Autodesk Fusion 360 part; units mm, degrees
(part 4 of 8)
sketch "SW4 upper stop 1 profile" plane through (0, -1.6638, 19.017) normal (0, -0.087156, 0.996195) x (1, 0, 0)
  line L0 (12.0897, 53.4995) -> (13.0897, 53.4995)
  line L1 (13.0897, 53.4995) -> (13.0897, 58.2995)
  line L2 (13.0897, 58.2995) -> (12.0897, 58.2995)
  line L3 (12.0897, 58.2995) -> (12.0897, 53.4995)
  dimension "d2300" = 12.0897
  dimension "d2301" = 53.4995
  dimension "d2302" = 1
  dimension "d2303" = 4.8
  constraint horizontal L0
  constraint vertical L1
  constraint horizontal L2
  constraint vertical L3
  measures "d2300" horizontal distance of origin L0.start
  measures "d2301" vertical distance of origin L0.start
  measures "d2302" distance of L0.start L0.end
  measures "d2303" distance of L0.end L1.end
extrude "SW4 upper stop 1" add sketch "SW4 upper stop 1 profile" along normal blind 0.8 bodies 2
sketch "SW4 upper stop 2 profile" plane through (0, -1.6638, 19.017) normal (0, -0.087156, 0.996195) x (1, 0, 0)
  line L0 (18.0897, 53.4995) -> (19.0897, 53.4995)
  line L1 (19.0897, 53.4995) -> (19.0897, 58.2995)
  line L2 (19.0897, 58.2995) -> (18.0897, 58.2995)
  line L3 (18.0897, 58.2995) -> (18.0897, 53.4995)
  dimension "d2306" = 18.0897
  dimension "d2307" = 53.4995
  dimension "d2308" = 1
  dimension "d2309" = 4.8
  constraint horizontal L0
  constraint vertical L1
  constraint horizontal L2
  constraint vertical L3
  measures "d2306" horizontal distance of origin L0.start
  measures "d2307" vertical distance of origin L0.start
  measures "d2308" distance of L0.start L0.end
  measures "d2309" distance of L0.end L1.end
extrude "SW4 upper stop 2" add sketch "SW4 upper stop 2 profile" along normal blind 0.8 bodies 2
sketch "SW4 wire exit 1 profile" plane through (0, -1.5592, 17.8216) normal (0, -0.087156, 0.996195) x (1, 0, 0)
  line L0 (6.2897, 44.3995) -> (10.074, 44.3995)
  line L1 (10.074, 44.3995) -> (10.074, 52.1995)
  line L2 (10.074, 52.1995) -> (6.2897, 52.1995)
  line L3 (6.2897, 52.1995) -> (6.2897, 44.3995)
  dimension "d2312" = 6.2897
  dimension "d2313" = 44.3995
  dimension "d2314" = 3.7843
  dimension "d2315" = 7.8
  constraint horizontal L0
  constraint vertical L1
  constraint horizontal L2
  constraint vertical L3
  measures "d2312" horizontal distance of origin L0.start
  measures "d2313" vertical distance of origin L0.start
  measures "d2314" distance of L0.start L0.end
  measures "d2315" distance of L0.end L1.end
extrude "SW4 wire exit 1" cut sketch "SW4 wire exit 1 profile" against normal blind 5 bodies 2
sketch "SW4 wire exit 2 profile" plane through (0, -1.5592, 17.8216) normal (0, -0.087156, 0.996195) x (1, 0, 0)
  line L0 (21.1055, 44.3995) -> (24.8897, 44.3995)
  line L1 (24.8897, 44.3995) -> (24.8897, 52.1995)
  line L2 (24.8897, 52.1995) -> (21.1055, 52.1995)
  line L3 (21.1055, 52.1995) -> (21.1055, 44.3995)
  dimension "d2318" = 21.1055
  dimension "d2319" = 44.3995
  dimension "d2320" = 3.7843
  dimension "d2321" = 7.8
  constraint horizontal L0
  constraint vertical L1
  constraint horizontal L2
  constraint vertical L3
  measures "d2318" horizontal distance of origin L0.start
  measures "d2319" vertical distance of origin L0.start
  measures "d2320" distance of L0.start L0.end
  measures "d2321" distance of L0.end L1.end
extrude "SW4 wire exit 2" cut sketch "SW4 wire exit 2 profile" against normal blind 5 bodies 2
sketch "SW4 support 1 reinforced stem profile" plane through (0, 0, 2) normal (0, 0, 1) x (1, 0, 0)
  line L0 (11.8897, 44.4226) -> (14.2897, 44.4226)
  line L1 (14.2897, 44.4226) -> (14.2897, 49.4226)
  line L2 (14.2897, 49.4226) -> (11.8897, 49.4226)
  line L3 (11.8897, 49.4226) -> (11.8897, 44.4226)
  dimension "d2324" = 11.8897
  dimension "d2325" = 44.4226
  dimension "d2326" = 2.4
  dimension "d2327" = 5
  constraint horizontal L0
  constraint vertical L1
  constraint horizontal L2
  constraint vertical L3
  measures "d2324" horizontal distance of origin L0.start
  measures "d2325" vertical distance of origin L0.start
  measures "d2326" distance of L0.start L0.end
  measures "d2327" distance of L0.end L1.end
extrude "SW4 support 1 reinforced stem" add sketch "SW4 support 1 reinforced stem profile" along normal blind 13.8471 bodies 3
sketch "SW4 support 1 profile" plane through (0, 0, 2) normal (0, 0, 1) x (1, 0, 0)
  line L0 (12.5897, 45.4226) -> (13.5897, 45.4226)
  line L1 (13.5897, 45.4226) -> (13.5897, 48.4226)
  line L2 (13.5897, 48.4226) -> (12.5897, 48.4226)
  line L3 (12.5897, 48.4226) -> (12.5897, 45.4226)
  dimension "d2330" = 12.5897
  dimension "d2331" = 45.4226
  dimension "d2332" = 1
  dimension "d2333" = 3
  constraint horizontal L0
  constraint vertical L1
  constraint horizontal L2
  constraint vertical L3
  measures "d2330" horizontal distance of origin L0.start
  measures "d2331" vertical distance of origin L0.start
  measures "d2332" distance of L0.start L0.end
  measures "d2333" distance of L0.end L1.end
extrude "SW4 support 1" add sketch "SW4 support 1 profile" along normal blind 16.3471 bodies 3
sketch "SW4 support 1 cap profile" plane through (0, -1.1931, 13.6376) normal (0, -0.087156, 0.996195) x (1, 0, 0)
  line L0 (12.4897, 46.2995) -> (13.6897, 46.2995)
  line L1 (13.6897, 46.2995) -> (13.6897, 50.2995)
  line L2 (13.6897, 50.2995) -> (12.4897, 50.2995)
  line L3 (12.4897, 50.2995) -> (12.4897, 46.2995)
  dimension "d2336" = 12.4897
  dimension "d2337" = 46.2995
  dimension "d2338" = 1.2
  dimension "d2339" = 4
  constraint horizontal L0
  constraint vertical L1
  constraint horizontal L2
  constraint vertical L3
  measures "d2336" horizontal distance of origin L0.start
  measures "d2337" vertical distance of origin L0.start
  measures "d2338" distance of L0.start L0.end
  measures "d2339" distance of L0.end L1.end
extrude "SW4 support 1 inclined cap" cut sketch "SW4 support 1 cap profile" along normal blind 39.0612 bodies 3
sketch "SW4 support 2 reinforced stem profile" plane through (0, 0, 2) normal (0, 0, 1) x (1, 0, 0)
  line L0 (16.8897, 44.4226) -> (19.2897, 44.4226)
  line L1 (19.2897, 44.4226) -> (19.2897, 49.4226)
  line L2 (19.2897, 49.4226) -> (16.8897, 49.4226)
  line L3 (16.8897, 49.4226) -> (16.8897, 44.4226)
  dimension "d2342" = 16.8897
  dimension "d2343" = 44.4226
  dimension "d2344" = 2.4
  dimension "d2345" = 5
  constraint horizontal L0
  constraint vertical L1
  constraint horizontal L2
  constraint vertical L3
  measures "d2342" horizontal distance of origin L0.start
  measures "d2343" vertical distance of origin L0.start
  measures "d2344" distance of L0.start L0.end
  measures "d2345" distance of L0.end L1.end
extrude "SW4 support 2 reinforced stem" add sketch "SW4 support 2 reinforced stem profile" along normal blind 13.8471 bodies 3
sketch "SW4 support 2 profile" plane through (0, 0, 2) normal (0, 0, 1) x (1, 0, 0)
  line L0 (17.5897, 45.4226) -> (18.5897, 45.4226)
  line L1 (18.5897, 45.4226) -> (18.5897, 48.4226)
  line L2 (18.5897, 48.4226) -> (17.5897, 48.4226)
  line L3 (17.5897, 48.4226) -> (17.5897, 45.4226)
  dimension "d2348" = 17.5897
  dimension "d2349" = 45.4226
  dimension "d2350" = 1
  dimension "d2351" = 3
  constraint horizontal L0
  constraint vertical L1
  constraint horizontal L2
  constraint vertical L3
  measures "d2348" horizontal distance of origin L0.start
  measures "d2349" vertical distance of origin L0.start
  measures "d2350" distance of L0.start L0.end
  measures "d2351" distance of L0.end L1.end
extrude "SW4 support 2" add sketch "SW4 support 2 profile" along normal blind 16.3471 bodies 3
sketch "SW4 support 2 cap profile" plane through (0, -1.1931, 13.6376) normal (0, -0.087156, 0.996195) x (1, 0, 0)
  line L0 (17.4897, 46.2995) -> (18.6897, 46.2995)
  line L1 (18.6897, 46.2995) -> (18.6897, 50.2995)
  line L2 (18.6897, 50.2995) -> (17.4897, 50.2995)
  line L3 (17.4897, 50.2995) -> (17.4897, 46.2995)
  dimension "d2354" = 17.4897
  dimension "d2355" = 46.2995
  dimension "d2356" = 1.2
  dimension "d2357" = 4
  constraint horizontal L0
  constraint vertical L1
  constraint horizontal L2
  constraint vertical L3
  measures "d2354" horizontal distance of origin L0.start
  measures "d2355" vertical distance of origin L0.start
  measures "d2356" distance of L0.start L0.end
  measures "d2357" distance of L0.end L1.end
extrude "SW4 support 2 inclined cap" cut sketch "SW4 support 2 cap profile" along normal blind 39.0612 bodies 3
sketch "SW5 receiver profile" plane through (0, -2.1431, 24.4961) normal (0, -0.087156, 0.996195) x (1, 0, 0)
  line L0 (30.8, 42.1972) -> (49.2, 42.1972)
  line L1 (49.2, 42.1972) -> (49.2, 59.7972)
  line L2 (49.2, 59.7972) -> (30.8, 59.7972)
  line L3 (30.8, 59.7972) -> (30.8, 42.1972)
  dimension "d2360" = 30.8
  dimension "d2361" = 42.1972
  dimension "d2362" = 18.4
  dimension "d2363" = 17.6
  constraint horizontal L0
  constraint vertical L1
  constraint horizontal L2
  constraint vertical L3
  measures "d2360" horizontal distance of origin L0.start
  measures "d2361" vertical distance of origin L0.start
  measures "d2362" distance of L0.start L0.end
  measures "d2363" distance of L0.end L1.end
extrude "SW5 integrated receiver" add sketch "SW5 receiver profile" against normal blind 11.5 bodies 2
sketch "SW5 switch lower clearance profile" plane through (0, -2.1431, 24.4961) normal (0, -0.087156, 0.996195) x (1, 0, 0)
  line L0 (32, 42.9972) -> (48, 42.9972)
  line L1 (48, 42.9972) -> (48, 58.9972)
  line L2 (48, 58.9972) -> (32, 58.9972)
  line L3 (32, 58.9972) -> (32, 42.9972)
  dimension "d2366" = 32
  dimension "d2367" = 42.9972
  dimension "d2368" = 16
  dimension "d2369" = 16
  constraint horizontal L0
  constraint vertical L1
  constraint horizontal L2
  constraint vertical L3
  measures "d2366" horizontal distance of origin L0.start
  measures "d2367" vertical distance of origin L0.start
  measures "d2368" distance of L0.start L0.end
  measures "d2369" distance of L0.end L1.end
extrude "SW5 switch lower clearance" cut sketch "SW5 switch lower clearance profile" against normal blind 5.5 bodies 2
sketch "SW5 holder pocket profile" plane through (0, -1.6638, 19.017) normal (0, -0.087156, 0.996195) x (1, 0, 0)
  line L0 (34.374, 44.425) -> (45.8055, 44.425)
  line L1 (45.8055, 44.425) -> (45.8055, 54.5741)
  line L2 (45.8055, 54.5741) -> (34.374, 54.5741)
  line L3 (34.374, 54.5741) -> (34.374, 44.425)
  dimension "d2372" = 34.374
  dimension "d2373" = 44.425
  dimension "d2374" = 11.4315
  dimension "d2375" = 10.1491
  constraint horizontal L0
  constraint vertical L1
  constraint horizontal L2
  constraint vertical L3
  measures "d2372" horizontal distance of origin L0.start
  measures "d2373" vertical distance of origin L0.start
  measures "d2374" distance of L0.start L0.end
  measures "d2375" distance of L0.end L1.end
extrude "SW5 open-bottom holder pocket" cut sketch "SW5 holder pocket profile" against normal blind 6.2 bodies 2
sketch "SW5 spring 1 release 1 profile" plane through (0, -2.056, 23.4999) normal (0, -0.087156, 0.996195) x (1, 0, 0)
  line L0 (30.7897, 51.5995) -> (34.374, 51.5995)
  line L1 (34.374, 51.5995) -> (34.374, 52.1995)
  line L2 (34.374, 52.1995) -> (30.7897, 52.1995)
  line L3 (30.7897, 52.1995) -> (30.7897, 51.5995)
  dimension "d2378" = 30.7897
  dimension "d2379" = 51.5995
  dimension "d2380" = 3.5843
  dimension "d2381" = 0.6
  constraint horizontal L0
  constraint vertical L1
  constraint horizontal L2
  constraint vertical L3
  measures "d2378" horizontal distance of origin L0.start
  measures "d2379" vertical distance of origin L0.start
  measures "d2380" distance of L0.start L0.end
  measures "d2381" distance of L0.end L1.end
extrude "SW5 spring 1 release 1" cut sketch "SW5 spring 1 release 1 profile" against normal blind 10.7 bodies 2
sketch "SW5 spring 1 release 2 profile" plane through (0, -2.056, 23.4999) normal (0, -0.087156, 0.996195) x (1, 0, 0)
  line L0 (30.7897, 54.1995) -> (34.374, 54.1995)
  line L1 (34.374, 54.1995) -> (34.374, 54.7995)
  line L2 (34.374, 54.7995) -> (30.7897, 54.7995)
  line L3 (30.7897, 54.7995) -> (30.7897, 54.1995)
  dimension "d2384" = 30.7897
  dimension "d2385" = 54.1995
  dimension "d2386" = 3.5843
  dimension "d2387" = 0.6
  constraint horizontal L0
  constraint vertical L1
  constraint horizontal L2
  constraint vertical L3
  measures "d2384" horizontal distance of origin L0.start
  measures "d2385" vertical distance of origin L0.start
  measures "d2386" distance of L0.start L0.end
  measures "d2387" distance of L0.end L1.end
extrude "SW5 spring 1 release 2" cut sketch "SW5 spring 1 release 2 profile" against normal blind 10.7 bodies 2
sketch "SW5 spring 1 inner clearance profile" plane through (0, -1.6638, 19.017) normal (0, -0.087156, 0.996195) x (1, 0, 0)
  line L0 (31.6897, 52.1995) -> (34.374, 52.1995)
  line L1 (34.374, 52.1995) -> (34.374, 54.1995)
  line L2 (34.374, 54.1995) -> (31.6897, 54.1995)
  line L3 (31.6897, 54.1995) -> (31.6897, 52.1995)
  dimension "d2390" = 31.6897
  dimension "d2391" = 52.1995
  dimension "d2392" = 2.6843
  dimension "d2393" = 2
  constraint horizontal L0
  constraint vertical L1
  constraint horizontal L2
  constraint vertical L3
  measures "d2390" horizontal distance of origin L0.start
  measures "d2391" vertical distance of origin L0.start
  measures "d2392" distance of L0.start L0.end
  measures "d2393" distance of L0.end L1.end
extrude "SW5 spring 1 inner clearance" cut sketch "SW5 spring 1 inner clearance profile" against normal blind 6.2 bodies 2
sketch "SW5 spring 1 hook profile" plane through (0, -1.2106, 13.8368) normal (0, -0.087156, 0.996195) x (1, 0, 0)
  line L0 (30.8897, 52.1995) -> (34.874, 52.1995)
  line L1 (34.874, 52.1995) -> (34.874, 54.1995)
  line L2 (34.874, 54.1995) -> (30.8897, 54.1995)
  line L3 (30.8897, 54.1995) -> (30.8897, 52.1995)
  dimension "d2396" = 30.8897
  dimension "d2397" = 52.1995
  dimension "d2398" = 3.9843
  dimension "d2399" = 2
  constraint horizontal L0
  constraint vertical L1
  constraint horizontal L2
  constraint vertical L3
  measures "d2396" horizontal distance of origin L0.start
  measures "d2397" vertical distance of origin L0.start
  measures "d2398" distance of L0.start L0.end
  measures "d2399" distance of L0.end L1.end
extrude "SW5 spring 1 retaining hook" add sketch "SW5 spring 1 hook profile" against normal blind 0.8 bodies 2
chamfer "SW5 spring 1 45 degree lead-in" distance 0.35 angle 45 1 edges at (34.874, 51.8562, 17.6765) tangent chain off on bodies 2
sketch "SW5 spring 2 release 1 profile" plane through (0, -2.056, 23.4999) normal (0, -0.087156, 0.996195) x (1, 0, 0)
  line L0 (45.8055, 51.5995) -> (49.3897, 51.5995)
  line L1 (49.3897, 51.5995) -> (49.3897, 52.1995)
  line L2 (49.3897, 52.1995) -> (45.8055, 52.1995)
  line L3 (45.8055, 52.1995) -> (45.8055, 51.5995)
  dimension "d2403" = 45.8055
  dimension "d2404" = 51.5995
  dimension "d2405" = 3.5843
  dimension "d2406" = 0.6
  constraint horizontal L0
  constraint vertical L1
  constraint horizontal L2
  constraint vertical L3
  measures "d2403" horizontal distance of origin L0.start
  measures "d2404" vertical distance of origin L0.start
  measures "d2405" distance of L0.start L0.end
  measures "d2406" distance of L0.end L1.end
extrude "SW5 spring 2 release 1" cut sketch "SW5 spring 2 release 1 profile" against normal blind 10.7 bodies 2
sketch "SW5 spring 2 release 2 profile" plane through (0, -2.056, 23.4999) normal (0, -0.087156, 0.996195) x (1, 0, 0)
  line L0 (45.8055, 54.1995) -> (49.3897, 54.1995)
  line L1 (49.3897, 54.1995) -> (49.3897, 54.7995)
  line L2 (49.3897, 54.7995) -> (45.8055, 54.7995)
  line L3 (45.8055, 54.7995) -> (45.8055, 54.1995)
  dimension "d2409" = 45.8055
  dimension "d2410" = 54.1995
  dimension "d2411" = 3.5843
  dimension "d2412" = 0.6
  constraint horizontal L0
  constraint vertical L1
  constraint horizontal L2
  constraint vertical L3
  measures "d2409" horizontal distance of origin L0.start
  measures "d2410" vertical distance of origin L0.start
  measures "d2411" distance of L0.start L0.end
  measures "d2412" distance of L0.end L1.end
extrude "SW5 spring 2 release 2" cut sketch "SW5 spring 2 release 2 profile" against normal blind 10.7 bodies 2
sketch "SW5 spring 2 inner clearance profile" plane through (0, -1.6638, 19.017) normal (0, -0.087156, 0.996195) x (1, 0, 0)
  line L0 (45.8055, 52.1995) -> (48.4897, 52.1995)
  line L1 (48.4897, 52.1995) -> (48.4897, 54.1995)
  line L2 (48.4897, 54.1995) -> (45.8055, 54.1995)
  line L3 (45.8055, 54.1995) -> (45.8055, 52.1995)
  dimension "d2415" = 45.8055
  dimension "d2416" = 52.1995
  dimension "d2417" = 2.6843
  dimension "d2418" = 2
  constraint horizontal L0
  constraint vertical L1
  constraint horizontal L2
  constraint vertical L3
  measures "d2415" horizontal distance of origin L0.start
  measures "d2416" vertical distance of origin L0.start
  measures "d2417" distance of L0.start L0.end
  measures "d2418" distance of L0.end L1.end
extrude "SW5 spring 2 inner clearance" cut sketch "SW5 spring 2 inner clearance profile" against normal blind 6.2 bodies 2
sketch "SW5 spring 2 hook profile" plane through (0, -1.2106, 13.8368) normal (0, -0.087156, 0.996195) x (1, 0, 0)
  line L0 (45.3055, 52.1995) -> (49.2897, 52.1995)
  line L1 (49.2897, 52.1995) -> (49.2897, 54.1995)
  line L2 (49.2897, 54.1995) -> (45.3055, 54.1995)
  line L3 (45.3055, 54.1995) -> (45.3055, 52.1995)
  dimension "d2421" = 45.3055
  dimension "d2422" = 52.1995
  dimension "d2423" = 3.9843
  dimension "d2424" = 2
  constraint horizontal L0
  constraint vertical L1
  constraint horizontal L2
  constraint vertical L3
  measures "d2421" horizontal distance of origin L0.start
  measures "d2422" vertical distance of origin L0.start
  measures "d2423" distance of L0.start L0.end
  measures "d2424" distance of L0.end L1.end
extrude "SW5 spring 2 retaining hook" add sketch "SW5 spring 2 hook profile" against normal blind 0.8 bodies 2
chamfer "SW5 spring 2 45 degree lead-in" distance 0.35 angle 45 1 edges at (45.3055, 51.8562, 17.6765) tangent chain off on bodies 2
sketch "SW5 upper stop 1 profile" plane through (0, -1.6638, 19.017) normal (0, -0.087156, 0.996195) x (1, 0, 0)
  line L0 (36.5897, 53.4995) -> (37.5897, 53.4995)
  line L1 (37.5897, 53.4995) -> (37.5897, 58.2995)
  line L2 (37.5897, 58.2995) -> (36.5897, 58.2995)
  line L3 (36.5897, 58.2995) -> (36.5897, 53.4995)
  dimension "d2428" = 36.5897
  dimension "d2429" = 53.4995
  dimension "d2430" = 1
  dimension "d2431" = 4.8
  constraint horizontal L0
  constraint vertical L1
  constraint horizontal L2
  constraint vertical L3
  measures "d2428" horizontal distance of origin L0.start
  measures "d2429" vertical distance of origin L0.start
  measures "d2430" distance of L0.start L0.end
  measures "d2431" distance of L0.end L1.end
extrude "SW5 upper stop 1" add sketch "SW5 upper stop 1 profile" along normal blind 0.8 bodies 2
sketch "SW5 upper stop 2 profile" plane through (0, -1.6638, 19.017) normal (0, -0.087156, 0.996195) x (1, 0, 0)
  line L0 (42.5897, 53.4995) -> (43.5897, 53.4995)
  line L1 (43.5897, 53.4995) -> (43.5897, 58.2995)
  line L2 (43.5897, 58.2995) -> (42.5897, 58.2995)
  line L3 (42.5897, 58.2995) -> (42.5897, 53.4995)
  dimension "d2434" = 42.5897
  dimension "d2435" = 53.4995
  dimension "d2436" = 1
  dimension "d2437" = 4.8
  constraint horizontal L0
  constraint vertical L1
  constraint horizontal L2
  constraint vertical L3
  measures "d2434" horizontal distance of origin L0.start
  measures "d2435" vertical distance of origin L0.start
  measures "d2436" distance of L0.start L0.end
  measures "d2437" distance of L0.end L1.end
extrude "SW5 upper stop 2" add sketch "SW5 upper stop 2 profile" along normal blind 0.8 bodies 2
sketch "SW5 wire exit 1 profile" plane through (0, -1.5592, 17.8216) normal (0, -0.087156, 0.996195) x (1, 0, 0)
  line L0 (30.7897, 44.3995) -> (34.574, 44.3995)
  line L1 (34.574, 44.3995) -> (34.574, 52.1995)
  line L2 (34.574, 52.1995) -> (30.7897, 52.1995)
  line L3 (30.7897, 52.1995) -> (30.7897, 44.3995)
  dimension "d2440" = 30.7897
  dimension "d2441" = 44.3995
  dimension "d2442" = 3.7843
  dimension "d2443" = 7.8
  constraint horizontal L0
  constraint vertical L1
  constraint horizontal L2
  constraint vertical L3
  measures "d2440" horizontal distance of origin L0.start
  measures "d2441" vertical distance of origin L0.start
  measures "d2442" distance of L0.start L0.end
  measures "d2443" distance of L0.end L1.end
extrude "SW5 wire exit 1" cut sketch "SW5 wire exit 1 profile" against normal blind 5 bodies 2
sketch "SW5 wire exit 2 profile" plane through (0, -1.5592, 17.8216) normal (0, -0.087156, 0.996195) x (1, 0, 0)
  line L0 (45.6055, 44.3995) -> (49.3897, 44.3995)
  line L1 (49.3897, 44.3995) -> (49.3897, 52.1995)
  line L2 (49.3897, 52.1995) -> (45.6055, 52.1995)
  line L3 (45.6055, 52.1995) -> (45.6055, 44.3995)
  dimension "d2446" = 45.6055
  dimension "d2447" = 44.3995
  dimension "d2448" = 3.7843
  dimension "d2449" = 7.8
  constraint horizontal L0
  constraint vertical L1
  constraint horizontal L2
  constraint vertical L3
  measures "d2446" horizontal distance of origin L0.start
  measures "d2447" vertical distance of origin L0.start
  measures "d2448" distance of L0.start L0.end
  measures "d2449" distance of L0.end L1.end
extrude "SW5 wire exit 2" cut sketch "SW5 wire exit 2 profile" against normal blind 5 bodies 2
sketch "SW5 support 1 reinforced stem profile" plane through (0, 0, 2) normal (0, 0, 1) x (1, 0, 0)
  line L0 (36.3897, 44.4226) -> (38.7897, 44.4226)
  line L1 (38.7897, 44.4226) -> (38.7897, 49.4226)
  line L2 (38.7897, 49.4226) -> (36.3897, 49.4226)
  line L3 (36.3897, 49.4226) -> (36.3897, 44.4226)
  dimension "d2452" = 36.3897
  dimension "d2453" = 44.4226
  dimension "d2454" = 2.4
  dimension "d2455" = 5
  constraint horizontal L0
  constraint vertical L1
  constraint horizontal L2
  constraint vertical L3
  measures "d2452" horizontal distance of origin L0.start
  measures "d2453" vertical distance of origin L0.start
  measures "d2454" distance of L0.start L0.end
  measures "d2455" distance of L0.end L1.end
extrude "SW5 support 1 reinforced stem" add sketch "SW5 support 1 reinforced stem profile" along normal blind 13.8471 bodies 3
sketch "SW5 support 1 profile" plane through (0, 0, 2) normal (0, 0, 1) x (1, 0, 0)
  line L0 (37.0897, 45.4226) -> (38.0897, 45.4226)
  line L1 (38.0897, 45.4226) -> (38.0897, 48.4226)
  line L2 (38.0897, 48.4226) -> (37.0897, 48.4226)
  line L3 (37.0897, 48.4226) -> (37.0897, 45.4226)
  dimension "d2458" = 37.0897
  dimension "d2459" = 45.4226
  dimension "d2460" = 1
  dimension "d2461" = 3
  constraint horizontal L0
  constraint vertical L1
  constraint horizontal L2
  constraint vertical L3
  measures "d2458" horizontal distance of origin L0.start
  measures "d2459" vertical distance of origin L0.start
  measures "d2460" distance of L0.start L0.end
  measures "d2461" distance of L0.end L1.end
extrude "SW5 support 1" add sketch "SW5 support 1 profile" along normal blind 16.3471 bodies 3
sketch "SW5 support 1 cap profile" plane through (0, -1.1931, 13.6376) normal (0, -0.087156, 0.996195) x (1, 0, 0)
  line L0 (36.9897, 46.2995) -> (38.1897, 46.2995)
  line L1 (38.1897, 46.2995) -> (38.1897, 50.2995)
  line L2 (38.1897, 50.2995) -> (36.9897, 50.2995)
  line L3 (36.9897, 50.2995) -> (36.9897, 46.2995)
  dimension "d2464" = 36.9897
  dimension "d2465" = 46.2995
  dimension "d2466" = 1.2
  dimension "d2467" = 4
  constraint horizontal L0
  constraint vertical L1
  constraint horizontal L2
  constraint vertical L3
  measures "d2464" horizontal distance of origin L0.start
  measures "d2465" vertical distance of origin L0.start
  measures "d2466" distance of L0.start L0.end
  measures "d2467" distance of L0.end L1.end
extrude "SW5 support 1 inclined cap" cut sketch "SW5 support 1 cap profile" along normal blind 39.0612 bodies 3
sketch "SW5 support 2 reinforced stem profile" plane through (0, 0, 2) normal (0, 0, 1) x (1, 0, 0)
  line L0 (41.3897, 44.4226) -> (43.7897, 44.4226)
  line L1 (43.7897, 44.4226) -> (43.7897, 49.4226)
  line L2 (43.7897, 49.4226) -> (41.3897, 49.4226)
  line L3 (41.3897, 49.4226) -> (41.3897, 44.4226)
  dimension "d2470" = 41.3897
  dimension "d2471" = 44.4226
  dimension "d2472" = 2.4
  dimension "d2473" = 5
  constraint horizontal L0
  constraint vertical L1
  constraint horizontal L2
  constraint vertical L3
  measures "d2470" horizontal distance of origin L0.start
  measures "d2471" vertical distance of origin L0.start
  measures "d2472" distance of L0.start L0.end
  measures "d2473" distance of L0.end L1.end
extrude "SW5 support 2 reinforced stem" add sketch "SW5 support 2 reinforced stem profile" along normal blind 13.8471 bodies 3
sketch "SW5 support 2 profile" plane through (0, 0, 2) normal (0, 0, 1) x (1, 0, 0)
  line L0 (42.0897, 45.4226) -> (43.0897, 45.4226)
  line L1 (43.0897, 45.4226) -> (43.0897, 48.4226)
  line L2 (43.0897, 48.4226) -> (42.0897, 48.4226)
  line L3 (42.0897, 48.4226) -> (42.0897, 45.4226)
  dimension "d2476" = 42.0897
  dimension "d2477" = 45.4226
  dimension "d2478" = 1
  dimension "d2479" = 3
  constraint horizontal L0
  constraint vertical L1
  constraint horizontal L2
  constraint vertical L3
  measures "d2476" horizontal distance of origin L0.start
  measures "d2477" vertical distance of origin L0.start
  measures "d2478" distance of L0.start L0.end
  measures "d2479" distance of L0.end L1.end
extrude "SW5 support 2" add sketch "SW5 support 2 profile" along normal blind 16.3471 bodies 3
sketch "SW5 support 2 cap profile" plane through (0, -1.1931, 13.6376) normal (0, -0.087156, 0.996195) x (1, 0, 0)
  line L0 (41.9897, 46.2995) -> (43.1897, 46.2995)
  line L1 (43.1897, 46.2995) -> (43.1897, 50.2995)
  line L2 (43.1897, 50.2995) -> (41.9897, 50.2995)
  line L3 (41.9897, 50.2995) -> (41.9897, 46.2995)
  dimension "d2482" = 41.9897
  dimension "d2483" = 46.2995
  dimension "d2484" = 1.2
  dimension "d2485" = 4
  constraint horizontal L0
  constraint vertical L1
  constraint horizontal L2
  constraint vertical L3
  measures "d2482" horizontal distance of origin L0.start
  measures "d2483" vertical distance of origin L0.start
  measures "d2484" distance of L0.start L0.end
  measures "d2485" distance of L0.end L1.end
extrude "SW5 support 2 inclined cap" cut sketch "SW5 support 2 cap profile" along normal blind 39.0612 bodies 3
sketch "SW6 receiver profile" plane through (0, -2.1431, 24.4961) normal (0, -0.087156, 0.996195) x (1, 0, 0)
  line L0 (55.3, 42.1972) -> (73.7, 42.1972)
  line L1 (73.7, 42.1972) -> (73.7, 59.7972)
  line L2 (73.7, 59.7972) -> (55.3, 59.7972)
  line L3 (55.3, 59.7972) -> (55.3, 42.1972)
  dimension "d2488" = 55.3
  dimension "d2489" = 42.1972
  dimension "d2490" = 18.4
  dimension "d2491" = 17.6
  constraint horizontal L0
  constraint vertical L1
  constraint horizontal L2
  constraint vertical L3
  measures "d2488" horizontal distance of origin L0.start
  measures "d2489" vertical distance of origin L0.start
  measures "d2490" distance of L0.start L0.end
  measures "d2491" distance of L0.end L1.end
extrude "SW6 integrated receiver" add sketch "SW6 receiver profile" against normal blind 11.5 bodies 2
sketch "SW6 switch lower clearance profile" plane through (0, -2.1431, 24.4961) normal (0, -0.087156, 0.996195) x (1, 0, 0)
  line L0 (56.5, 42.9972) -> (72.5, 42.9972)
  line L1 (72.5, 42.9972) -> (72.5, 58.9972)
  line L2 (72.5, 58.9972) -> (56.5, 58.9972)
  line L3 (56.5, 58.9972) -> (56.5, 42.9972)
  dimension "d2494" = 56.5
  dimension "d2495" = 42.9972
  dimension "d2496" = 16
  dimension "d2497" = 16
  constraint horizontal L0
  constraint vertical L1
  constraint horizontal L2
  constraint vertical L3
  measures "d2494" horizontal distance of origin L0.start
  measures "d2495" vertical distance of origin L0.start
  measures "d2496" distance of L0.start L0.end
  measures "d2497" distance of L0.end L1.end
extrude "SW6 switch lower clearance" cut sketch "SW6 switch lower clearance profile" against normal blind 5.5 bodies 2
sketch "SW6 holder pocket profile" plane through (0, -1.6638, 19.017) normal (0, -0.087156, 0.996195) x (1, 0, 0)
  line L0 (58.874, 44.425) -> (70.3055, 44.425)
  line L1 (70.3055, 44.425) -> (70.3055, 54.5741)
  line L2 (70.3055, 54.5741) -> (58.874, 54.5741)
  line L3 (58.874, 54.5741) -> (58.874, 44.425)
  dimension "d2500" = 58.874
  dimension "d2501" = 44.425
  dimension "d2502" = 11.4315
  dimension "d2503" = 10.1491
  constraint horizontal L0
  constraint vertical L1
  constraint horizontal L2
  constraint vertical L3
  measures "d2500" horizontal distance of origin L0.start
  measures "d2501" vertical distance of origin L0.start
  measures "d2502" distance of L0.start L0.end
  measures "d2503" distance of L0.end L1.end
extrude "SW6 open-bottom holder pocket" cut sketch "SW6 holder pocket profile" against normal blind 6.2 bodies 2
sketch "SW6 spring 1 release 1 profile" plane through (0, -2.056, 23.4999) normal (0, -0.087156, 0.996195) x (1, 0, 0)
  line L0 (55.2897, 51.5995) -> (58.874, 51.5995)
  line L1 (58.874, 51.5995) -> (58.874, 52.1995)
  line L2 (58.874, 52.1995) -> (55.2897, 52.1995)
  line L3 (55.2897, 52.1995) -> (55.2897, 51.5995)
  dimension "d2506" = 55.2897
  dimension "d2507" = 51.5995
  dimension "d2508" = 3.5843
  dimension "d2509" = 0.6
  constraint horizontal L0
  constraint vertical L1
  constraint horizontal L2
  constraint vertical L3
  measures "d2506" horizontal distance of origin L0.start
  measures "d2507" vertical distance of origin L0.start
  measures "d2508" distance of L0.start L0.end
  measures "d2509" distance of L0.end L1.end
extrude "SW6 spring 1 release 1" cut sketch "SW6 spring 1 release 1 profile" against normal blind 10.7 bodies 2
sketch "SW6 spring 1 release 2 profile" plane through (0, -2.056, 23.4999) normal (0, -0.087156, 0.996195) x (1, 0, 0)
  line L0 (55.2897, 54.1995) -> (58.874, 54.1995)
  line L1 (58.874, 54.1995) -> (58.874, 54.7995)
  line L2 (58.874, 54.7995) -> (55.2897, 54.7995)
  line L3 (55.2897, 54.7995) -> (55.2897, 54.1995)
  dimension "d2512" = 55.2897
  dimension "d2513" = 54.1995
  dimension "d2514" = 3.5843
  dimension "d2515" = 0.6
  constraint horizontal L0
  constraint vertical L1
  constraint horizontal L2
  constraint vertical L3
  measures "d2512" horizontal distance of origin L0.start
  measures "d2513" vertical distance of origin L0.start
  measures "d2514" distance of L0.start L0.end
  measures "d2515" distance of L0.end L1.end
extrude "SW6 spring 1 release 2" cut sketch "SW6 spring 1 release 2 profile" against normal blind 10.7 bodies 2
sketch "SW6 spring 1 inner clearance profile" plane through (0, -1.6638, 19.017) normal (0, -0.087156, 0.996195) x (1, 0, 0)
  line L0 (56.1897, 52.1995) -> (58.874, 52.1995)
  line L1 (58.874, 52.1995) -> (58.874, 54.1995)
  line L2 (58.874, 54.1995) -> (56.1897, 54.1995)
  line L3 (56.1897, 54.1995) -> (56.1897, 52.1995)
  dimension "d2518" = 56.1897
  dimension "d2519" = 52.1995
  dimension "d2520" = 2.6843
  dimension "d2521" = 2
  constraint horizontal L0
  constraint vertical L1
  constraint horizontal L2
  constraint vertical L3
  measures "d2518" horizontal distance of origin L0.start
  measures "d2519" vertical distance of origin L0.start
  measures "d2520" distance of L0.start L0.end
  measures "d2521" distance of L0.end L1.end
extrude "SW6 spring 1 inner clearance" cut sketch "SW6 spring 1 inner clearance profile" against normal blind 6.2 bodies 2
sketch "SW6 spring 1 hook profile" plane through (0, -1.2106, 13.8368) normal (0, -0.087156, 0.996195) x (1, 0, 0)
  line L0 (55.3897, 52.1995) -> (59.374, 52.1995)
  line L1 (59.374, 52.1995) -> (59.374, 54.1995)
  line L2 (59.374, 54.1995) -> (55.3897, 54.1995)
  line L3 (55.3897, 54.1995) -> (55.3897, 52.1995)
  dimension "d2524" = 55.3897
  dimension "d2525" = 52.1995
  dimension "d2526" = 3.9843
  dimension "d2527" = 2
  constraint horizontal L0
  constraint vertical L1
  constraint horizontal L2
  constraint vertical L3
  measures "d2524" horizontal distance of origin L0.start
  measures "d2525" vertical distance of origin L0.start
  measures "d2526" distance of L0.start L0.end
  measures "d2527" distance of L0.end L1.end
extrude "SW6 spring 1 retaining hook" add sketch "SW6 spring 1 hook profile" against normal blind 0.8 bodies 2
chamfer "SW6 spring 1 45 degree lead-in" distance 0.35 angle 45 1 edges at (59.374, 51.8562, 17.6765) tangent chain off on bodies 2
sketch "SW6 spring 2 release 1 profile" plane through (0, -2.056, 23.4999) normal (0, -0.087156, 0.996195) x (1, 0, 0)
  line L0 (70.3055, 51.5995) -> (73.8897, 51.5995)
  line L1 (73.8897, 51.5995) -> (73.8897, 52.1995)
  line L2 (73.8897, 52.1995) -> (70.3055, 52.1995)
  line L3 (70.3055, 52.1995) -> (70.3055, 51.5995)
  dimension "d2531" = 70.3055
  dimension "d2532" = 51.5995
  dimension "d2533" = 3.5843
  dimension "d2534" = 0.6
  constraint horizontal L0
  constraint vertical L1
  constraint horizontal L2
  constraint vertical L3
  measures "d2531" horizontal distance of origin L0.start
  measures "d2532" vertical distance of origin L0.start
  measures "d2533" distance of L0.start L0.end
  measures "d2534" distance of L0.end L1.end
extrude "SW6 spring 2 release 1" cut sketch "SW6 spring 2 release 1 profile" against normal blind 10.7 bodies 2
sketch "SW6 spring 2 release 2 profile" plane through (0, -2.056, 23.4999) normal (0, -0.087156, 0.996195) x (1, 0, 0)
  line L0 (70.3055, 54.1995) -> (73.8897, 54.1995)
  line L1 (73.8897, 54.1995) -> (73.8897, 54.7995)
  line L2 (73.8897, 54.7995) -> (70.3055, 54.7995)
  line L3 (70.3055, 54.7995) -> (70.3055, 54.1995)
  dimension "d2537" = 70.3055
  dimension "d2538" = 54.1995
  dimension "d2539" = 3.5843
  dimension "d2540" = 0.6
  constraint horizontal L0
  constraint vertical L1
  constraint horizontal L2
  constraint vertical L3
  measures "d2537" horizontal distance of origin L0.start
  measures "d2538" vertical distance of origin L0.start
  measures "d2539" distance of L0.start L0.end
  measures "d2540" distance of L0.end L1.end
extrude "SW6 spring 2 release 2" cut sketch "SW6 spring 2 release 2 profile" against normal blind 10.7 bodies 2
sketch "SW6 spring 2 inner clearance profile" plane through (0, -1.6638, 19.017) normal (0, -0.087156, 0.996195) x (1, 0, 0)
  line L0 (70.3055, 52.1995) -> (72.9897, 52.1995)
  line L1 (72.9897, 52.1995) -> (72.9897, 54.1995)
  line L2 (72.9897, 54.1995) -> (70.3055, 54.1995)
  line L3 (70.3055, 54.1995) -> (70.3055, 52.1995)
  dimension "d2543" = 70.3055
  dimension "d2544" = 52.1995
  dimension "d2545" = 2.6843
  dimension "d2546" = 2
  constraint horizontal L0
  constraint vertical L1
  constraint horizontal L2
  constraint vertical L3
  measures "d2543" horizontal distance of origin L0.start
  measures "d2544" vertical distance of origin L0.start
  measures "d2545" distance of L0.start L0.end
  measures "d2546" distance of L0.end L1.end
extrude "SW6 spring 2 inner clearance" cut sketch "SW6 spring 2 inner clearance profile" against normal blind 6.2 bodies 2
sketch "SW6 spring 2 hook profile" plane through (0, -1.2106, 13.8368) normal (0, -0.087156, 0.996195) x (1, 0, 0)
  line L0 (69.8055, 52.1995) -> (73.7897, 52.1995)
  line L1 (73.7897, 52.1995) -> (73.7897, 54.1995)
  line L2 (73.7897, 54.1995) -> (69.8055, 54.1995)
  line L3 (69.8055, 54.1995) -> (69.8055, 52.1995)
  dimension "d2549" = 69.8055
  dimension "d2550" = 52.1995
  dimension "d2551" = 3.9843
  dimension "d2552" = 2
  constraint horizontal L0
  constraint vertical L1
  constraint horizontal L2
  constraint vertical L3
  measures "d2549" horizontal distance of origin L0.start
  measures "d2550" vertical distance of origin L0.start
  measures "d2551" distance of L0.start L0.end
  measures "d2552" distance of L0.end L1.end
extrude "SW6 spring 2 retaining hook" add sketch "SW6 spring 2 hook profile" against normal blind 0.8 bodies 2
chamfer "SW6 spring 2 45 degree lead-in" distance 0.35 angle 45 1 edges at (69.8055, 51.8562, 17.6765) tangent chain off on bodies 2
sketch "SW6 upper stop 1 profile" plane through (0, -1.6638, 19.017) normal (0, -0.087156, 0.996195) x (1, 0, 0)
  line L0 (61.0897, 53.4995) -> (62.0897, 53.4995)
  line L1 (62.0897, 53.4995) -> (62.0897, 58.2995)
  line L2 (62.0897, 58.2995) -> (61.0897, 58.2995)
  line L3 (61.0897, 58.2995) -> (61.0897, 53.4995)
  dimension "d2556" = 61.0897
  dimension "d2557" = 53.4995
  dimension "d2558" = 1
  dimension "d2559" = 4.8
  constraint horizontal L0
  constraint vertical L1
  constraint horizontal L2
  constraint vertical L3
  measures "d2556" horizontal distance of origin L0.start
  measures "d2557" vertical distance of origin L0.start
  measures "d2558" distance of L0.start L0.end
  measures "d2559" distance of L0.end L1.end
extrude "SW6 upper stop 1" add sketch "SW6 upper stop 1 profile" along normal blind 0.8 bodies 2
sketch "SW6 upper stop 2 profile" plane through (0, -1.6638, 19.017) normal (0, -0.087156, 0.996195) x (1, 0, 0)
  line L0 (67.0897, 53.4995) -> (68.0897, 53.4995)
  line L1 (68.0897, 53.4995) -> (68.0897, 58.2995)
  line L2 (68.0897, 58.2995) -> (67.0897, 58.2995)
  line L3 (67.0897, 58.2995) -> (67.0897, 53.4995)
  dimension "d2562" = 67.0897
  dimension "d2563" = 53.4995
  dimension "d2564" = 1
  dimension "d2565" = 4.8
  constraint horizontal L0
  constraint vertical L1
  constraint horizontal L2
  constraint vertical L3
  measures "d2562" horizontal distance of origin L0.start
  measures "d2563" vertical distance of origin L0.start
  measures "d2564" distance of L0.start L0.end
  measures "d2565" distance of L0.end L1.end
extrude "SW6 upper stop 2" add sketch "SW6 upper stop 2 profile" along normal blind 0.8 bodies 2
sketch "SW6 wire exit 1 profile" plane through (0, -1.5592, 17.8216) normal (0, -0.087156, 0.996195) x (1, 0, 0)
  line L0 (55.2897, 44.3995) -> (59.074, 44.3995)
  line L1 (59.074, 44.3995) -> (59.074, 52.1995)
  line L2 (59.074, 52.1995) -> (55.2897, 52.1995)
  line L3 (55.2897, 52.1995) -> (55.2897, 44.3995)
  dimension "d2568" = 55.2897
  dimension "d2569" = 44.3995
  dimension "d2570" = 3.7843
  dimension "d2571" = 7.8
  constraint horizontal L0
  constraint vertical L1
  constraint horizontal L2
  constraint vertical L3
  measures "d2568" horizontal distance of origin L0.start
  measures "d2569" vertical distance of origin L0.start
  measures "d2570" distance of L0.start L0.end
  measures "d2571" distance of L0.end L1.end
extrude "SW6 wire exit 1" cut sketch "SW6 wire exit 1 profile" against normal blind 5 bodies 2
sketch "SW6 wire exit 2 profile" plane through (0, -1.5592, 17.8216) normal (0, -0.087156, 0.996195) x (1, 0, 0)
  line L0 (70.1055, 44.3995) -> (73.8897, 44.3995)
  line L1 (73.8897, 44.3995) -> (73.8897, 52.1995)
  line L2 (73.8897, 52.1995) -> (70.1055, 52.1995)
  line L3 (70.1055, 52.1995) -> (70.1055, 44.3995)
  dimension "d2574" = 70.1055
  dimension "d2575" = 44.3995
  dimension "d2576" = 3.7843
  dimension "d2577" = 7.8
  constraint horizontal L0
  constraint vertical L1
  constraint horizontal L2
  constraint vertical L3
  measures "d2574" horizontal distance of origin L0.start
  measures "d2575" vertical distance of origin L0.start
  measures "d2576" distance of L0.start L0.end
  measures "d2577" distance of L0.end L1.end
extrude "SW6 wire exit 2" cut sketch "SW6 wire exit 2 profile" against normal blind 5 bodies 2
sketch "SW6 support 1 reinforced stem profile" plane through (0, 0, 2) normal (0, 0, 1) x (1, 0, 0)
  line L0 (60.8897, 44.4226) -> (63.2897, 44.4226)
  line L1 (63.2897, 44.4226) -> (63.2897, 49.4226)
  line L2 (63.2897, 49.4226) -> (60.8897, 49.4226)
  line L3 (60.8897, 49.4226) -> (60.8897, 44.4226)
  dimension "d2580" = 60.8897
  dimension "d2581" = 44.4226
  dimension "d2582" = 2.4
  dimension "d2583" = 5
  constraint horizontal L0
  constraint vertical L1
  constraint horizontal L2
  constraint vertical L3
  measures "d2580" horizontal distance of origin L0.start
  measures "d2581" vertical distance of origin L0.start
  measures "d2582" distance of L0.start L0.end
  measures "d2583" distance of L0.end L1.end
extrude "SW6 support 1 reinforced stem" add sketch "SW6 support 1 reinforced stem profile" along normal blind 13.8471 bodies 3
sketch "SW6 support 1 profile" plane through (0, 0, 2) normal (0, 0, 1) x (1, 0, 0)
  line L0 (61.5897, 45.4226) -> (62.5897, 45.4226)
  line L1 (62.5897, 45.4226) -> (62.5897, 48.4226)
  line L2 (62.5897, 48.4226) -> (61.5897, 48.4226)
  line L3 (61.5897, 48.4226) -> (61.5897, 45.4226)
  dimension "d2586" = 61.5897
  dimension "d2587" = 45.4226
  dimension "d2588" = 1
  dimension "d2589" = 3
  constraint horizontal L0
  constraint vertical L1
  constraint horizontal L2
  constraint vertical L3
  measures "d2586" horizontal distance of origin L0.start
  measures "d2587" vertical distance of origin L0.start
  measures "d2588" distance of L0.start L0.end
  measures "d2589" distance of L0.end L1.end
extrude "SW6 support 1" add sketch "SW6 support 1 profile" along normal blind 16.3471 bodies 3
sketch "SW6 support 1 cap profile" plane through (0, -1.1931, 13.6376) normal (0, -0.087156, 0.996195) x (1, 0, 0)
  line L0 (61.4897, 46.2995) -> (62.6897, 46.2995)
  line L1 (62.6897, 46.2995) -> (62.6897, 50.2995)
  line L2 (62.6897, 50.2995) -> (61.4897, 50.2995)
  line L3 (61.4897, 50.2995) -> (61.4897, 46.2995)
  dimension "d2592" = 61.4897
  dimension "d2593" = 46.2995
  dimension "d2594" = 1.2
  dimension "d2595" = 4
  constraint horizontal L0
  constraint vertical L1
  constraint horizontal L2
  constraint vertical L3
  measures "d2592" horizontal distance of origin L0.start
  measures "d2593" vertical distance of origin L0.start
  measures "d2594" distance of L0.start L0.end
  measures "d2595" distance of L0.end L1.end
extrude "SW6 support 1 inclined cap" cut sketch "SW6 support 1 cap profile" along normal blind 39.0612 bodies 3
sketch "SW6 support 2 reinforced stem profile" plane through (0, 0, 2) normal (0, 0, 1) x (1, 0, 0)
  line L0 (65.8897, 44.4226) -> (68.2897, 44.4226)
  line L1 (68.2897, 44.4226) -> (68.2897, 49.4226)
  line L2 (68.2897, 49.4226) -> (65.8897, 49.4226)
  line L3 (65.8897, 49.4226) -> (65.8897, 44.4226)
  dimension "d2598" = 65.8897
  dimension "d2599" = 44.4226
  dimension "d2600" = 2.4
  dimension "d2601" = 5
  constraint horizontal L0
  constraint vertical L1
  constraint horizontal L2
  constraint vertical L3
  measures "d2598" horizontal distance of origin L0.start
  measures "d2599" vertical distance of origin L0.start
  measures "d2600" distance of L0.start L0.end
  measures "d2601" distance of L0.end L1.end
extrude "SW6 support 2 reinforced stem" add sketch "SW6 support 2 reinforced stem profile" along normal blind 13.8471 bodies 3
sketch "SW6 support 2 profile" plane through (0, 0, 2) normal (0, 0, 1) x (1, 0, 0)
  line L0 (66.5897, 45.4226) -> (67.5897, 45.4226)
  line L1 (67.5897, 45.4226) -> (67.5897, 48.4226)
  line L2 (67.5897, 48.4226) -> (66.5897, 48.4226)
  line L3 (66.5897, 48.4226) -> (66.5897, 45.4226)
  dimension "d2604" = 66.5897
  dimension "d2605" = 45.4226
  dimension "d2606" = 1
  dimension "d2607" = 3
  constraint horizontal L0
  constraint vertical L1
  constraint horizontal L2
  constraint vertical L3
  measures "d2604" horizontal distance of origin L0.start
  measures "d2605" vertical distance of origin L0.start
  measures "d2606" distance of L0.start L0.end
  measures "d2607" distance of L0.end L1.end
extrude "SW6 support 2" add sketch "SW6 support 2 profile" along normal blind 16.3471 bodies 3
sketch "SW6 support 2 cap profile" plane through (0, -1.1931, 13.6376) normal (0, -0.087156, 0.996195) x (1, 0, 0)
  line L0 (66.4897, 46.2995) -> (67.6897, 46.2995)
  line L1 (67.6897, 46.2995) -> (67.6897, 50.2995)
  line L2 (67.6897, 50.2995) -> (66.4897, 50.2995)
  line L3 (66.4897, 50.2995) -> (66.4897, 46.2995)
  dimension "d2610" = 66.4897
  dimension "d2611" = 46.2995
  dimension "d2612" = 1.2
  dimension "d2613" = 4
  constraint horizontal L0
  constraint vertical L1
  constraint horizontal L2
  constraint vertical L3
  measures "d2610" horizontal distance of origin L0.start
  measures "d2611" vertical distance of origin L0.start
  measures "d2612" distance of L0.start L0.end
  measures "d2613" distance of L0.end L1.end
extrude "SW6 support 2 inclined cap" cut sketch "SW6 support 2 cap profile" along normal blind 39.0612 bodies 3
sketch "OLED clearance after switch receivers profile" plane through (0, -2.2739, 25.9904) normal (0, -0.087156, 0.996195) x (1, 0, 0)
  line L0 (5.55, 59.2972) -> (41.95, 59.2972)
  line L1 (41.95, 59.2972) -> (41.95, 93.6972)
  line L2 (41.95, 93.6972) -> (5.55, 93.6972)
  line L3 (5.55, 93.6972) -> (5.55, 59.2972)
  dimension "d2616" = 5.55
  dimension "d2617" = 59.2972
  dimension "d2618" = 36.4
  dimension "d2619" = 34.4
  constraint horizontal L0
  constraint vertical L1
  constraint horizontal L2
  constraint vertical L3
  measures "d2616" horizontal distance of origin L0.start
  measures "d2617" vertical distance of origin L0.start
  measures "d2618" distance of L0.start L0.end
  measures "d2619" distance of L0.end L1.end
extrude "OLED clearance after switch receivers" cut sketch "OLED clearance after switch receivers profile" against normal blind 1.8 bodies 2
sketch "Switch trial plate profile" plane through (0, -2.2739, 25.9904) normal (0, -0.087156, 0.996195) x (1, 0, 0)
  line L0 (104, 15.4972) -> (126, 15.4972)
  line L1 (126, 15.4972) -> (126, 37.4972)
  line L2 (126, 37.4972) -> (104, 37.4972)
  line L3 (104, 37.4972) -> (104, 15.4972)
  dimension "d2622" = 104
  dimension "d2623" = 15.4972
  dimension "d2624" = 22
  dimension "d2625" = 22
  constraint horizontal L0
  constraint vertical L1
  constraint horizontal L2
  constraint vertical L3
  measures "d2622" horizontal distance of origin L0.start
  measures "d2623" vertical distance of origin L0.start
  measures "d2624" distance of L0.start L0.end
  measures "d2625" distance of L0.end L1.end
extrude "Switch trial plate" add sketch "Switch trial plate profile" against normal blind 1.5 separate body makes body 5
sketch "Switch trial clip seat profile" plane through (0, -2.2739, 25.9904) normal (0, -0.087156, 0.996195) x (1, 0, 0)
  line L0 (107.95, 19.4472) -> (122.05, 19.4472)
  line L1 (122.05, 19.4472) -> (122.05, 33.5472)
  line L2 (122.05, 33.5472) -> (107.95, 33.5472)
  line L3 (107.95, 33.5472) -> (107.95, 19.4472)
  dimension "d2628" = 107.95
  dimension "d2629" = 19.4472
  dimension "d2630" = 14.1
  dimension "d2631" = 14.1
  constraint horizontal L0
  constraint vertical L1
  constraint horizontal L2
  constraint vertical L3
  measures "d2628" horizontal distance of origin L0.start
  measures "d2629" vertical distance of origin L0.start
  measures "d2630" distance of L0.start L0.end
  measures "d2631" distance of L0.end L1.end
extrude "Switch trial clip seat" cut sketch "Switch trial clip seat profile" against normal blind 1.6 bodies 5
sketch "Switch trial receiver profile" plane through (0, -2.1431, 24.4961) normal (0, -0.087156, 0.996195) x (1, 0, 0)
  line L0 (105.8, 17.6972) -> (124.2, 17.6972)
  line L1 (124.2, 17.6972) -> (124.2, 35.2972)
  line L2 (124.2, 35.2972) -> (105.8, 35.2972)
  line L3 (105.8, 35.2972) -> (105.8, 17.6972)
  dimension "d2634" = 105.8
  dimension "d2635" = 17.6972
  dimension "d2636" = 18.4
  dimension "d2637" = 17.6
  constraint horizontal L0
  constraint vertical L1
  constraint horizontal L2
  constraint vertical L3
  measures "d2634" horizontal distance of origin L0.start
  measures "d2635" vertical distance of origin L0.start
  measures "d2636" distance of L0.start L0.end
  measures "d2637" distance of L0.end L1.end
extrude "Switch trial integrated receiver" add sketch "Switch trial receiver profile" against normal blind 11.5 bodies 5
sketch "Switch trial switch lower clearance profile" plane through (0, -2.1431, 24.4961) normal (0, -0.087156, 0.996195) x (1, 0, 0)
  line L0 (107, 18.4972) -> (123, 18.4972)
  line L1 (123, 18.4972) -> (123, 34.4972)
  line L2 (123, 34.4972) -> (107, 34.4972)
  line L3 (107, 34.4972) -> (107, 18.4972)
  dimension "d2640" = 107
  dimension "d2641" = 18.4972
  dimension "d2642" = 16
  dimension "d2643" = 16
  constraint horizontal L0
  constraint vertical L1
  constraint horizontal L2
  constraint vertical L3
  measures "d2640" horizontal distance of origin L0.start
  measures "d2641" vertical distance of origin L0.start
  measures "d2642" distance of L0.start L0.end
  measures "d2643" distance of L0.end L1.end
extrude "Switch trial switch lower clearance" cut sketch "Switch trial switch lower clearance profile" against normal blind 5.5 bodies 5
sketch "Switch trial holder pocket profile" plane through (0, -1.6638, 19.017) normal (0, -0.087156, 0.996195) x (1, 0, 0)
  line L0 (109.374, 19.925) -> (120.8055, 19.925)
  line L1 (120.8055, 19.925) -> (120.8055, 30.0741)
  line L2 (120.8055, 30.0741) -> (109.374, 30.0741)
  line L3 (109.374, 30.0741) -> (109.374, 19.925)
  dimension "d2646" = 109.374
  dimension "d2647" = 19.925
  dimension "d2648" = 11.4315
  dimension "d2649" = 10.1491
  constraint horizontal L0
  constraint vertical L1
  constraint horizontal L2
  constraint vertical L3
  measures "d2646" horizontal distance of origin L0.start
  measures "d2647" vertical distance of origin L0.start
  measures "d2648" distance of L0.start L0.end
  measures "d2649" distance of L0.end L1.end
extrude "Switch trial open-bottom holder pocket" cut sketch "Switch trial holder pocket profile" against normal blind 6.2 bodies 5